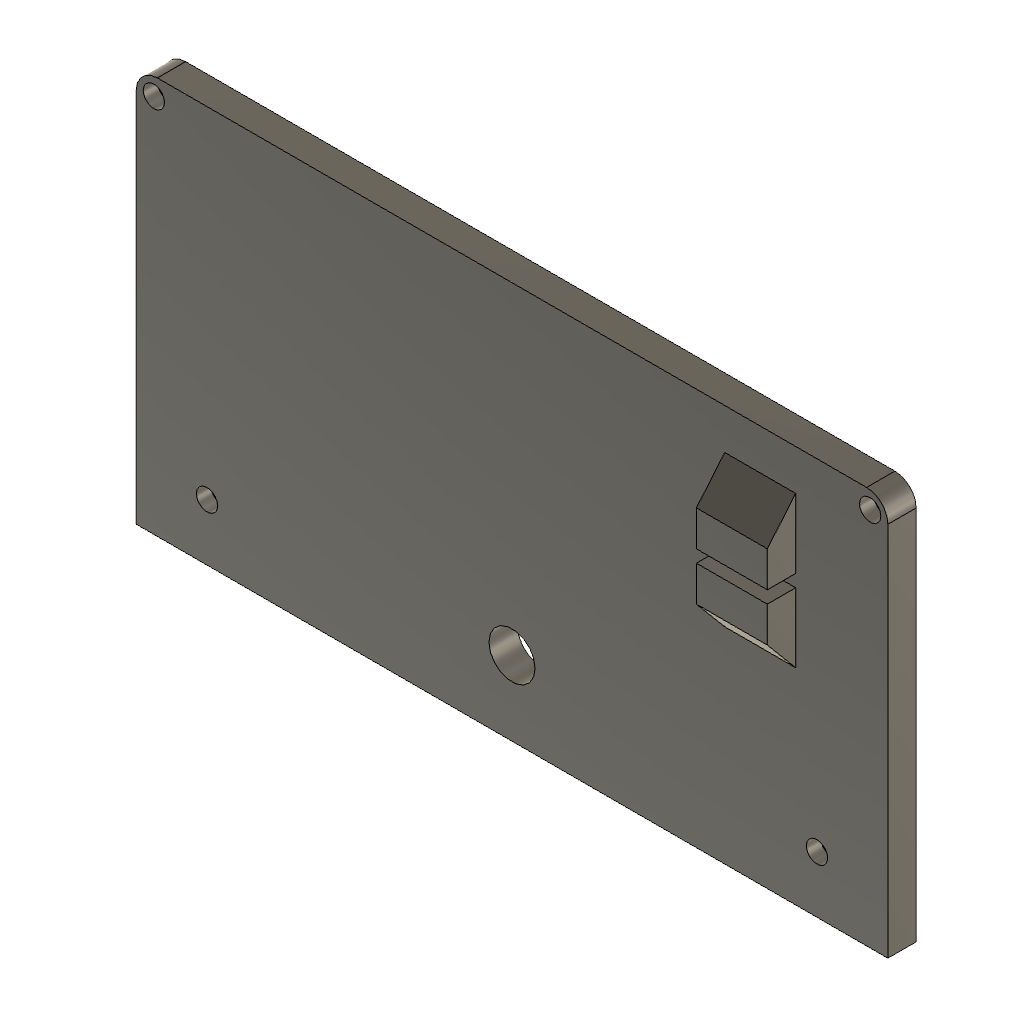
Clock Back (Autodesk Fusion 360 design; units mm, degrees)
Autodesk Fusion 360 part; units mm, degrees
sketch "Sketch1" plane through (0, 0, 0) normal (0, 1, 0) x (1, 0, 0)
  line L0 (106, -56) -> (-106, -56)
  line L1 (-106, -56) -> (-106, 56)
  line L2 (-106, 56) -> (106, 56)
  line L3 (106, 56) -> (106, -56)
  line L4 (106, -56) -> (-106, 56) construction
  line L5 (-106, -56) -> (106, 56) construction
  line L6 (-106, -56) -> (-101, -56)
  line L7 (-101, -56) -> (-101, -51)
  line L8 (-101, -51) -> (-106, -51)
  line L9 (-106, -51) -> (-106, -56)
  line L10 (106, -56) -> (101, -56)
  line L11 (101, -56) -> (101, -51)
  line L12 (101, -51) -> (106, -51)
  line L13 (106, -51) -> (106, -56)
  circle A0 centre (-101, -51) radius 2
  circle A1 centre (-101, -51) radius 3
  circle A2 centre (101, -51) radius 2
  circle A3 centre (101, -51) radius 3
  circle A4 centre (0, 35) radius 6.5
  line L14 (-106, 56) -> (-101, 56)
  line L15 (-101, 56) -> (-101, -56)
  line L16 (-101, -56) -> (-106, -56)
  line L17 (-106, -56) -> (-106, 56)
  line L18 (106, 56) -> (101, 56)
  line L19 (101, 56) -> (101, -56)
  line L20 (101, -56) -> (106, -56)
  line L21 (106, -56) -> (106, 56)
  line L22 (-106, 56) -> (106, 56)
  line L23 (106, 56) -> (106, 50)
  line L24 (106, 50) -> (-106, 50)
  line L25 (-106, 50) -> (-106, 56)
  line L26 (-101, 50) -> (-86, 50)
  line L27 (-86, 50) -> (-86, 40)
  line L28 (-86, 40) -> (-101, 40)
  line L29 (-101, 40) -> (-101, 50)
  line L30 (101, 50) -> (86, 50)
  line L31 (86, 50) -> (86, 40)
  line L32 (86, 40) -> (101, 40)
  line L33 (101, 40) -> (101, 50)
  circle A5 centre (86, 40) radius 2
  circle A6 centre (86, 40) radius 3
  circle A7 centre (-86, 40) radius 2
  circle A8 centre (-86, 40) radius 3
  dimension "d1" = 212
  dimension "d2" = 112
  dimension "d3" = 5
  dimension "d4" = 5
  dimension "d5" = 5
  dimension "d6" = 5
  dimension "d7" = 4
  dimension "d8" = 6
  dimension "d9" = 4
  dimension "d10" = 6
  dimension "d16" = 13
  dimension "d19" = 5
  dimension "d20" = 5
  dimension "d21" = 6
  dimension "d22" = 15
  dimension "d23" = 10
  dimension "d24" = 15
  dimension "d25" = 10
  dimension "d26" = 4
  dimension "d27" = 6
  dimension "d28" = 4
  dimension "d29" = 6
  constraint horizontal L0
  constraint perpendicular L0 L1
  constraint parallel L0 L2
  constraint parallel L1 L3
  constraint coincident L4 origin
  constraint coincident L5 origin
  constraint horizontal L6
  constraint vertical L7
  constraint horizontal L8
  constraint vertical L9
  constraint horizontal L10
  constraint vertical L11
  constraint horizontal L12
  constraint vertical L13
  constraint coincident L7.end L8.start
  constraint concentric A0 A1
  constraint coincident L11.end L12.start
  constraint concentric A2 A3
  constraint horizontal L14
  constraint vertical L15
  constraint horizontal L16
  constraint vertical L17
  constraint horizontal L18
  constraint vertical L19
  constraint horizontal L20
  constraint vertical L21
  constraint horizontal L22
  constraint vertical L23
  constraint horizontal L24
  constraint vertical L25
  constraint horizontal L26
  constraint vertical L27
  constraint horizontal L28
  constraint vertical L29
  constraint coincident L24 L26.start
  constraint coincident L15 L26.start
  constraint horizontal L30
  constraint vertical L31
  constraint horizontal L32
  constraint vertical L33
  constraint coincident L24 L30.start
  constraint coincident L19 L30.start
  constraint coincident L31.end L32.start
  constraint concentric A5 A6
  constraint coincident L27.end L28.start
  constraint concentric A7 A8
  measures "d1" distance of L1.end L2.end
  measures "d2" distance of L0.end L1.end
  measures "d3" distance of L0.end L6.end
  measures "d4" distance of L0.end L8.end
  measures "d5" distance of L0.start L10.end
  measures "d6" distance of L0.start L12.end
  measures "d7" diameter of A0
  measures "d8" diameter of A1
  measures "d9" diameter of A2
  measures "d10" diameter of A3
  measures "d16" diameter of A4
  measures "d19" distance of L1.end L14.end
  measures "d20" distance of L2.end L18.end
  measures "d21" distance of L1.end L24.end
  measures "d22" distance of L26.start L26.end
  measures "d23" distance of L26.start L28.end
  measures "d24" distance of L30.start L30.end
  measures "d25" distance of L30.start L32.end
  measures "d26" diameter of A5
  measures "d27" diameter of A6
  measures "d28" diameter of A7
  measures "d29" diameter of A8
extrude "Extrude1" add sketch "Sketch1" along normal blind 6 contours L0 L3 L10 L11 L12 L13 A3 L19 L20 L21 | L0 L7 L11 A1 A3 L15 L19 L24 L27 L28 L31 L32 A6 A8 | L3 L12 A3 L19 L21 L24 L33 | L0 L1 L6 L7 L8 L9 A1 L15 L16 L17 | L11 A2 A3 L19 | L11 L12 A2 A3 L19 | L2 L3 L18 L19 L21 L22 L23 L24 | L12 A2 A3 L19 | L7 L8 A0 A1 L15 | L7 A0 A1 L15 | L2 L15 L19 L22 L24 L26 L30 | L19 L24 L30 L31 L32 L33 A6 | L1 L8 A1 L15 L17 L24 L29 | L8 A0 A1 L15 | L1 L2 L14 L15 L17 L22 L24 L25 | L31 L32 A5 A6 | L31 L32 A5 A6 | L15 L24 L26 L27 L28 L29 A8 | L27 L28 A7 A8 | L27 L28 A7 A8 | A4
extrude "Extrude2" cut sketch "Sketch1" along normal blind 4 contours L11 A2 A3 L19 | L11 L12 A2 A3 L19 | L12 A2 A3 L19 | L7 L8 A0 A1 L15 | L7 A0 A1 L15 | L8 A0 A1 L15 | L31 L32 A5 A6 | L31 L32 A5 A6 | L27 L28 A7 A8 | L27 L28 A7 A8
extrude "Extrude3" cut sketch "Sketch1" along normal blind 6 contours A4
fillet "Fillet1" radius 6 2 edges at (106, 3, 56) (-106, 3, 56)
sketch "Sketch4" plane through (0, 0, 0) normal (0, -1, 0) x (1, 0, 0)
  circle A0 centre (0, -35) radius 6.5
  arc A1 (-100, 56) -> (-106, 50) centre (-100, 50) ccw
  line L0 (-106, 50) -> (-106, -56)
  line L1 (-106, -56) -> (106, -56)
  line L2 (106, -56) -> (106, 50)
  arc A2 (106, 50) -> (100, 56) centre (100, 50) ccw
  line L3 (100, 56) -> (-100, 56)
  circle A3 centre (86, -40) radius 3
  circle A4 centre (-101, 51) radius 3
  circle A5 centre (-86, -40) radius 3
  circle A6 centre (101, 51) radius 3
  line L4 (60, 35) -> (80, 35)
  line L5 (80, 35) -> (80, 25)
  line L6 (80, 25) -> (60, 25)
  line L7 (60, 25) -> (60, 35)
  line L8 (60, 25) -> (80, 25)
  line L9 (80, 25) -> (80, 21.5)
  line L10 (80, 21.5) -> (60, 21.5)
  line L11 (60, 21.5) -> (60, 25)
  line L12 (60, 21.5) -> (80, 21.5)
  line L13 (80, 21.5) -> (80, 11.5)
  line L14 (80, 11.5) -> (60, 11.5)
  line L15 (60, 11.5) -> (60, 21.5)
  point P0 (60, 35)
  point P1 (60, 25)
  point P2 (80, 25)
  dimension "d40" = 3.5
  dimension "d41" = 10
  constraint horizontal L4
  constraint vertical L5
  constraint horizontal L6
  constraint vertical L7
  constraint horizontal L8
  constraint vertical L9
  constraint horizontal L10
  constraint vertical L11
  constraint horizontal L12
  constraint vertical L13
  constraint horizontal L14
  constraint vertical L15
  measures "d40" distance of P1 L10.end
  measures "d41" distance of L10.end L14.end
extrude "Extrude6" add sketch "Sketch4" along normal blind 8 contours L4 L5 L6 L7 L8 | L10 L12 L13 L14 L15
sketch "Sketch5" plane through (60, 0, 0) normal (-1, 0, 0) x (0, -1, 0)
  line L0 (0, 35) -> (0, 25)
  line L1 (0, 25) -> (8, 25)
  line L2 (8, 25) -> (8, 35)
  line L3 (8, 35) -> (0, 35)
  line L4 (8, 35) -> (-2.477, 47.486)
  line L5 (8, 35) -> (24.2993, 35) construction
  line L6 (8, 11.5) -> (-3.0854, -1.7111)
  line L7 (8, 11.5) -> (25.2459, 11.5) construction
  line L8 (0, 50) -> (0, -56)
  line L9 (8, 11.5) -> (0, 11.5)
  point P0 (8, 11.5)
  point P1 (0, 11.5)
  dimension "d44" = 130
  dimension "d45" = 130
  constraint horizontal L5
  constraint coincident L2.end L3.start
  constraint horizontal L7
  constraint coincident P0 L6.start
  constraint coincident P1 L9.end
  measures "d44" angle of L4 L5
  measures "d45" angle of L6 L7
extrude "Extrude7" add sketch "Sketch5" against normal blind 20 contours L3 L4 L8 | L6 L8 L9
extrude "Extrude8" add 1 faces at (0.1485, 6, 24.7251) along direction (0, 1, 0) blind 2
